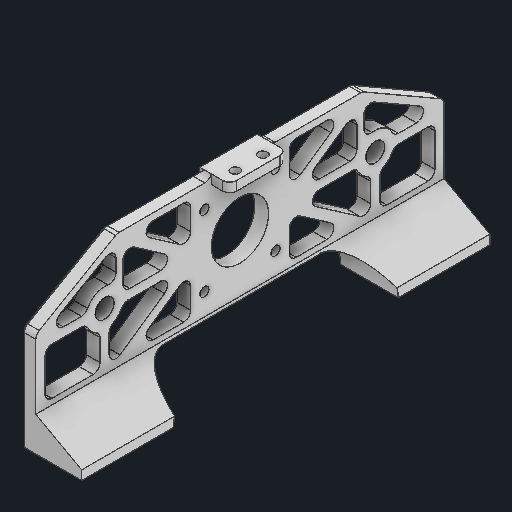
# Autodesk Inventor part: stand_v2
Saved by Autodesk Inventor 2026.3 (Build 303398000, 398)
## iProperties
Created: 2026-04-22
Part Number: stand_v2
Material: 일반
Document SubType Name: Modeling
Designer: khw
Density: 1 g/cm^3
Appearance: 기본값
Author: khw
Autodesk Inventor part; units mm, degrees
ref_plane "YZ Plane" through (0, 0, 0) normal (1, 0, 0) x (0, 1, 0)
ref_plane "XZ Plane" through (0, 0, 0) normal (0, 1, 0) x (-1, 0, 0)
ref_plane "XY Plane" through (0, 0, 0) normal (0, 0, 1) x (1, 0, 0)
sketch "스케치1" plane through (0, 0, 0) normal (1, 0, 0) x (0, 1, 0)
  circle A0 centre (0, 0) radius 12.5
  line L0 (-15.5, 15.5) -> (15.5, 15.5) construction
  line L1 (15.5, 15.5) -> (15.5, -15.5) construction
  line L2 (15.5, -15.5) -> (-15.5, -15.5) construction
  line L3 (-15.5, -15.5) -> (-15.5, 15.5) construction
  line L4 (-15.5, 15.5) -> (15.5, -15.5) construction
  line L5 (15.5, 15.5) -> (-15.5, -15.5) construction
  circle A1 centre (15.5, 15.5) radius 2
  circle A2 centre (15.5, -15.5) radius 2
  circle A3 centre (-15.5, -15.5) radius 2
  circle A4 centre (-15.5, 15.5) radius 2
  line L6 (0, 0) -> (0, -59) construction
  circle A5 centre (0, -59) radius 4.15
  line L7 (25.5, 0) -> (25.5, -53.493)
  line L8 (25.5, -53.493) -> (5, -89)
  line L9 (5, -89) -> (-40, -89)
  line L10 (-25.5, 0) -> (-25.5, -34.5)
  arc A6 (-40, -49) -> (-25.5, -34.5) centre (-40, -34.5) ccw
  line L11 (-40, -49) -> (-40, -89)
  line L12 (22.5, -21.5) -> (2, -21.5)
  line L13 (2, -21.5) -> (2, -51)
  line L14 (2, -51) -> (22.5, -51)
  line L15 (22.5, -51) -> (22.5, -21.5)
  circle A7 centre (0, -59) radius 8.2462
  line L16 (21.7432, -54) -> (6.5574, -54)
  line L17 (21.7432, -54) -> (2, -88.1962)
  line L18 (2, -88.1962) -> (2, -67)
  line L19 (-2, -67) -> (-2, -85)
  line L20 (-2, -85) -> (-22.5, -85)
  line L21 (-22.5, -85) -> (-22.5, -21.5)
  line L22 (-22.5, -21.5) -> (-2, -21.5)
  line L23 (-2, -51) -> (-2, -21.5)
  line L24 (2, -21.5) -> (22.5, -51) construction
  line L25 (4.4355, -21.5) -> (22.5, -47.4953)
  line L26 (2, -25.0047) -> (22.5, -54.5047)
  line L27 (-2, -21.5) -> (-22.5, -51) construction
  line L28 (-4.4355, -21.5) -> (-22.5, -47.4953)
  line L29 (-2, -25.0047) -> (-22.5, -54.5047)
  line L30 (-8.2462, -59) -> (-22.5, -59) construction
  line L31 (-8, -57) -> (-22.5, -57)
  line L32 (-8, -61) -> (-22.5, -61)
  line L33 (0, 0) -> (25.5, 0) construction
  line L34 (0, 0) -> (0, 59) construction
  circle A8 centre (0, 59) radius 4.15
  line L35 (25.5, 0) -> (25.5, 53.493)
  line L36 (25.5, 53.493) -> (5, 89)
  line L37 (5, 89) -> (-40, 89)
  line L38 (-25.5, 0) -> (-25.5, 34.5)
  arc A9 (-25.5, 34.5) -> (-40, 49) centre (-40, 34.5) ccw
  line L39 (-40, 49) -> (-40, 89)
  line L40 (22.5, 21.5) -> (2, 21.5)
  line L41 (2, 21.5) -> (2, 51)
  line L42 (2, 51) -> (22.5, 51)
  line L43 (22.5, 51) -> (22.5, 21.5)
  circle A10 centre (0, 59) radius 8.2462
  line L44 (21.7432, 54) -> (6.5574, 54)
  line L45 (21.7432, 54) -> (2, 88.1962)
  line L46 (2, 88.1962) -> (2, 67)
  line L47 (-2, 67) -> (-2, 85)
  line L48 (-2, 85) -> (-22.5, 85)
  line L49 (-22.5, 85) -> (-22.5, 21.5)
  line L50 (-22.5, 21.5) -> (-2, 21.5)
  line L51 (-2, 51) -> (-2, 21.5)
  line L52 (2, 21.5) -> (22.5, 51) construction
  line L53 (4.4355, 21.5) -> (22.5, 47.4953)
  line L54 (2, 25.0047) -> (22.5, 54.5047)
  line L55 (-2, 25.0047) -> (-22.5, 54.5047)
  line L56 (-2, 21.5) -> (-22.5, 51) construction
  line L57 (-4.4355, 21.5) -> (-22.5, 47.4953)
  line L58 (-8.2462, 59) -> (-22.5, 59) construction
  line L59 (-8, 57) -> (-22.5, 57)
  line L60 (-8, 61) -> (-22.5, 61)
  point P0 (20.0645, -51)
  point P1 (20.0645, 51)
  dimension "d0" = 25
  dimension "d1" = 31
  dimension "d2" = 31
  dimension "d3" = 4
  dimension "d4" = 4
  dimension "d5" = 4
  dimension "d6" = 4
  dimension "d7" = 59
  dimension "d8" = 8.3
  dimension "d9" = 10
  dimension "d10" = 10
  dimension "d11" = 40
  dimension "d12" = 40
  dimension "d13" = 45
  dimension "d14" = 120
  dimension "d15" = 30
  dimension "d16" = 2
  dimension "d17" = 3
  dimension "d18" = 6
  dimension "d19" = 8
  dimension "d20" = 3
  dimension "d21" = 3
  dimension "d22" = 2
  dimension "d24" = 3
  dimension "d25" = 2
  dimension "d26" = 4
  dimension "d27" = 4
  dimension "d28" = 2
  dimension "d29" = 2
  dimension "d30" = 26
  dimension "d31" = 2
  dimension "d32" = 2
  constraints: 122 end point, 43 symmetric about line, 10 parallel, 10 point on line, 9 centre point, 7 perpendicular, 6 coincident, 6 horizontal, 5 vertical, 4 point on circle, 2 midpoint, 1 collinear, 1 line through centre, 1 tangent, 22 other
  measures "d0" diameter of A0
  measures "d1" distance of L1.end L2.end
  measures "d2" distance of L0.end L1.end
  measures "d3" diameter of A1
  measures "d4" diameter of A2
  measures "d5" diameter of A3
  measures "d6" diameter of A4
  measures "d7" distance of L6.start L6.end
  measures "d8" diameter of A5
  measures "d9" distance between parallel lines of L7 L1
  measures "d10" distance between parallel lines of L10 L3
  measures "d11" distance between parallel lines of L11 L6
  measures "d12" distance of L11.start L9.end
  measures "d13" distance of L8.end L9.end
  measures "d14" angle of L9 L8
  measures "d15" distance from line of L6.end L9
  measures "d16" distance between parallel lines of L13 L6
  measures "d17" distance between parallel lines of L7 L15
  measures "d18" distance from line of L1.end L12
  measures "d19" distance from line of A5.centre L14
  measures "d20" distance between parallel lines of L8 L17
  measures "d21" distance between parallel lines of L14 L16
  measures "d22" distance between parallel lines of L6 L18
  measures "d24" distance between parallel lines of L10 L21
  measures "d25" distance between parallel lines of L6 L23
  measures "d26" distance between parallel lines of L18 L19
  measures "d27" distance between parallel lines of L9 L20
  measures "d28" distance between parallel lines of L24 L25
  measures "d29" distance between parallel lines of L24 L26
  measures "d30" distance between parallel lines of L20 L30
  measures "d31" distance between parallel lines of L30 L31
  measures "d32" distance between parallel lines of L30 L32
extrude "돌출1" add sketch "스케치1" along normal blind 6 contours L7 L8 L9 L11 A6 L10 L38 A9 L39 L37 L36 L35 | A7 | L25 L15 L14 L26 L13 L12 | A7 L32 L21 L31 | L29 L21 L28 L22 L23 | A10 | L40 L41 L54 L42 L43 L53 | L59 L49 L60 A10 | L51 L50 L57 L49 L55
fillet "모깎기1" radius 3 50 edges at (3, 2, -25.0047) (3, 22.5, -21.5) (3, 25.5, -53.493) (3, -2, -67) (3, 5, -89) (3, 4.4355, -21.5) (3, -22.5, 54.5047) (3, -8, 57) (3, -22.5, 57) (3, -2, 51) (3, -2, 25.0047) (3, 21.7432, 54) (3, 2, 25.0047) (3, 2, 51) (3, 22.5, 21.5) (3, 4.4355, 21.5) (3, 20.0645, 51) (3, 6.5574, 54) (3, 2, 67) (3, -8, 61) (3, -4.4355, 21.5) (3, -22.5, 21.5) (3, -22.5, 47.4953) (3, 2, 88.1962) (3, -22.5, 61) (3, -22.5, 85) (3, -2, 85) (3, -2, 67) (3, 25.5, 53.493) (3, 5, 89) (3, 22.5, 47.4953) (3, 22.5, -47.4953) (3, 2, -51) (3, 20.0645, -51) (3, -22.5, -21.5) (3, -4.4355, -21.5) (3, -2, -25.0047) (3, -2, -51) (3, -22.5, -54.5047) (3, -22.5, -57) (3, -8, -57) (3, -8, -61) (3, 2, -67) (3, -22.5, -47.4953) (3, 21.7432, -54) (3, 6.5574, -54) (3, 2, -88.1962) (3, -22.5, -61) (3, -2, -85) (3, -22.5, -85)
sketch "스케치2" plane through (6, -40, -89) normal (0, 0, -1) x (-1, 0, 0)
  line L0 (6, 0) -> (0, 0) projected
  line L1 (0, 0) -> (-20, 0)
  line L2 (-20, 0) -> (-20, 4)
  line L3 (-20, 4) -> (0, 15)
  line L4 (0, 43.2679) -> (6, 43.2679) projected
  line L5 (0, 0) -> (0, 43.2679) projected
  line L6 (6, 0) -> (0, 0) projected
  line L7 (6, 0) -> (6, 43.2679) projected
  point P0 (6, 40)
  dimension "d36" = 15
  dimension "d37" = 4
  dimension "d38" = 20
  constraints: 6 end point, 1 horizontal, 1 perpendicular, 1 point on line
  measures "d36" distance of L0.end L3.end
  measures "d37" distance of L1.end L2.end
  measures "d38" distance of L0.end L1.end
extrude "돌출2" add sketch "스케치2" against normal up to surface (178 mm away) contours L1 L2 L3 L5
sketch "스케치3" plane through (0, 0, 0) normal (-1, 0, 0) x (0, 0, 1)
  arc A0 (-34.5, -25.5) -> (-49, -40) centre (-34.5, -40) ccw projected
  line L0 (-49, -40) -> (49, -40) projected
  arc A1 (49, -40) -> (34.5, -25.5) centre (34.5, -40) ccw projected
  line L1 (34.5, -25.5) -> (-34.5, -25.5) projected
  point P0 (0, 0)
extrude "돌출3" cut sketch "스케치3" against normal through all
chamfer "모따기1" distance 1 angle 45 14 edges at (0, -29.747, -44.753) (0, -25.5, 0) (0, -29.747, 44.753) (0, -40, -69) (0, -18.366, -89) (0, 4.7679, -88.5981) (0, 15.4821, -70.8446) (0, 25.3978, -53.4656) (0, 25.5, 0) (0, 25.3978, 53.4656) (0, 15.4821, 70.8446) (0, 4.7679, 88.5981) (0, -18.366, 89) (0, -40, 69)
sketch "스케치4" plane through (6, 25.5, 52.6891) normal (0, 1, 0) x (1, 0, 0)
  line L0 (-5, 0) -> (-5, 105.3782) projected
  line L1 (-5, 52.6891) -> (9.9682, 52.6891) construction
  line L2 (-5, 0) -> (-5, 105.3782) projected
  line L3 (0, 0) -> (-5, 0) projected
  line L4 (0, 105.3782) -> (0, 0) projected
  line L5 (-5, 105.3782) -> (0, 105.3782) projected
  line L6 (8, 40.1891) -> (0, 40.1891)
  line L7 (0, 40.1891) -> (0, 65.1891)
  line L8 (0, 65.1891) -> (8, 65.1891)
  line L9 (8, 65.1891) -> (8, 40.1891)
  line L10 (8, 40.1891) -> (0, 65.1891) construction
  line L11 (0, 40.1891) -> (8, 65.1891) construction
  line L12 (4, 46.6891) -> (4, 58.6891) construction
  circle A0 centre (4, 46.6891) radius 2
  circle A1 centre (4, 58.6891) radius 2
  line L13 (0, 65.1891) -> (-6, 65.1891) projected
  line L14 (0, 40.1891) -> (-5, 40.1891)
  line L15 (-5, 40.1891) -> (-5, 65.1891)
  line L16 (-5, 65.1891) -> (0, 65.1891)
  line L17 (0, 65.1891) -> (0, 40.1891)
  line L18 (-6, 65.1891) -> (-6, 40.1891) projected
  line L19 (-5, 40.1891) -> (-6, 40.1891)
  line L20 (-6, 40.1891) -> (-6, 65.1891)
  line L21 (-6, 65.1891) -> (-5, 65.1891)
  line L22 (-5, 65.1891) -> (-5, 40.1891)
  point P0 (-6, 52.6891)
  point P1 (4, 52.6891)
  dimension "d47" = 25
  dimension "d48" = 12
  dimension "d49" = 4
  dimension "d50" = 4
  dimension "d51" = 4
  constraints: 32 end point, 6 parallel, 4 horizontal, 4 midpoint, 4 point on line, 3 perpendicular, 2 centre point, 2 coincident, 1 vertical
  measures "d47" distance of L8.end L6.start
  measures "d48" distance of L12.start L12.end
  measures "d49" diameter of A0
  measures "d50" diameter of A1
  measures "d51" distance from line of L9 L12.start
extrude "돌출4" add sketch "스케치4" along normal mid plane 4 contours L19 L18 L13 L0 | L0 L13 L4 L14 | L4 L8 L9 L6
fillet "모깎기2" radius 3 4 edges at (3.5, 25.5, -12.5) (14, 25.5, -12.5) (14, 25.5, 12.5) (3.5, 25.5, 12.5)
chamfer "모따기2" distance 1 angle 45 3 edges at (0, 27.5, 0) (0, 26, -12.5) (0, 26, 12.5)
